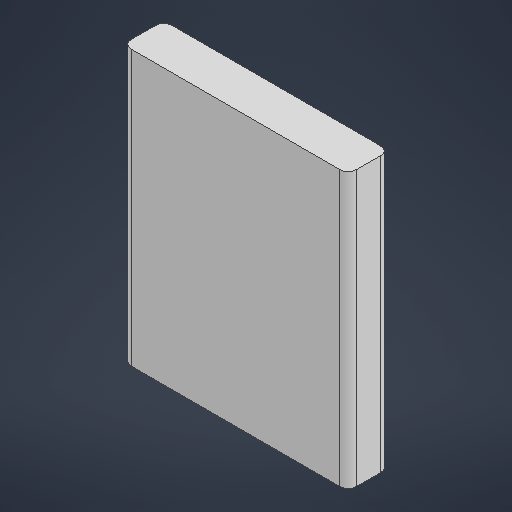
# Autodesk Inventor part: 电池
Saved by Autodesk Inventor 2025 (Build 290162000, 162)
## iProperties
Created: 2025-12-04
Part Number: 电池
Material: 常规
Document SubType Name: Modeling
Designer: HZD
Density: 1 g/cm^3
Appearance: 默认
Author: HZD
Autodesk Inventor part; units mm, degrees
ref_plane "YZ Plane" through (0, 0, 0) normal (1, 0, 0) x (0, 1, 0)
ref_plane "XZ Plane" through (0, 0, 0) normal (0, 1, 0) x (-1, 0, 0)
ref_plane "XY Plane" through (0, 0, 0) normal (0, 0, 1) x (1, 0, 0)
sketch "草图1" plane through (0, 0, 0) normal (0, 0, 1) x (1, 0, 0)
  line L0 (27.5, -33.5) -> (-27.5, -33.5)
  line L1 (-27.5, -33.5) -> (-27.5, 33.5)
  line L2 (-27.5, 33.5) -> (27.5, 33.5)
  line L3 (27.5, 33.5) -> (27.5, -33.5)
  line L4 (27.5, -33.5) -> (-27.5, 33.5) construction
  line L5 (-27.5, -33.5) -> (27.5, 33.5) construction
  point P0 (0, 0)
  dimension "d0" = 67
  dimension "d1" = 55
  constraints: 12 end point, 2 midpoint, 2 parallel, 1 horizontal, 1 perpendicular
  measures "d0" distance of L2.end L0.start
  measures "d1" distance of L1.end L2.end
extrude "拉伸1" add sketch "草图1" along normal blind 10
fillet "圆角1" radius 2 4 edges at (-27.5, 0, 10) (-27.5, 0, 0) (27.5, 0, 10) (27.5, 0, 0)
